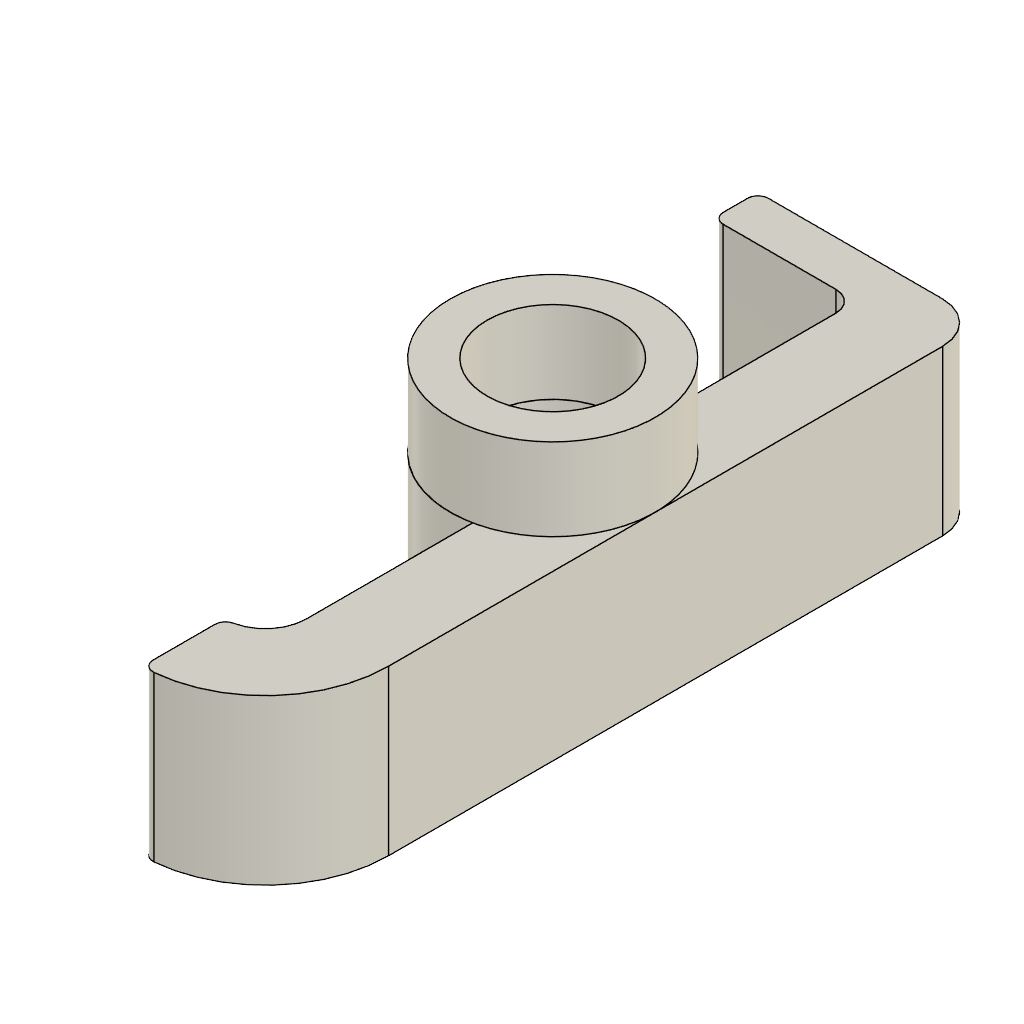
Top_Assembly_110626 (Autodesk Fusion 360 archive; units mm, degrees)
design "Bumper Flag"
part number: 2026-11-05-18-53-03-409
Autodesk Fusion 360 part; units mm, degrees
note: some values were not read from the file. Set by a fixed rule: which sketch regions a step uses.
sketch "Sketch1" plane through (0, 0, 0) normal (0, 0, 1) x (1, 0, 0)
  circle A0 centre (0, 0) radius 3.2
  line L0 (0, 0) -> (3.2, 0) construction
  circle A1 centre (0, 0) radius 5
  line L1 (3.2, 0) -> (5, 0) construction
  line L2 (5, 0) -> (5, -13)
  line L3 (5, -13) -> (-1, -13) construction
  arc A2 (-1, -19) -> (5, -13) centre (-1, -13) ccw
  line L4 (-1, -13) -> (-1, -19) construction
  line L5 (1, 4.899) -> (1, -13)
  arc A3 (-1, -15) -> (1, -13) centre (-1, -13) ccw
  line L6 (5, 0) -> (5, 16)
  line L7 (1, 4.899) -> (1, 13.8)
  line L8 (5, 16) -> (-6, 16)
  line L9 (1, 13.8) -> (-6, 13.8)
  line L10 (-6, 13.8) -> (-6, 16)
  circle A4 centre (-136.9792, 82.2137) radius 166.5 construction
  line L11 (-136.9792, 82.2137) -> (29.5208, 82.2137) construction
  line L12 (-136.9792, 82.2137) -> (0, 0) construction
  line L13 (0, 0) -> (5.7813, -3.4699) construction
  line L14 (0.2, 82.2137) -> (0.2, 15.461) construction
  line L15 (29.5208, 82.2137) -> (35.0208, 82.2137) construction
  line L16 (0.2, 15.461) -> (0.2, 12.961) construction
  line L17 (0.2, 12.961) -> (-5.8, 12.961) construction
  line L18 (-5.8, 12.961) -> (-5.8, 17.961) construction
  line L19 (0.2, 15.461) -> (-5.8, 15.461) construction
  line L20 (0.2, 17.961) -> (-5.8, 17.961) construction
  line L21 (-54.9792, 82.2137) -> (-54.9792, -11.7863) construction
  line L22 (-54.9792, -11.7863) -> (0.448, -11.7863) construction
  line L23 (-136.9792, 82.2137) -> (-136.9792, -89.7863) construction
  arc A5 (-136.9792, -89.7863) -> (-136.9792, 254.2137) centre (-136.9792, 82.2137) ccw
  line L24 (-136.9792, 82.2137) -> (-136.9792, 254.2137) construction
  line L25 (-136.9792, 82.2137) -> (-1, -13) construction
  line L26 (-1, -13) -> (3.9149, -16.4415) construction
  line L27 (4.5077, -2.1636) -> (-1.1176, -13.8835) construction
  line L28 (0, 0) -> (4.5077, -2.1636) construction
  line L29 (-1.1176, -13.8835) -> (-6.5268, -11.2872) construction
  arc A6 (-9.1231, -16.6964) -> (-1.1176, -13.8835) centre (-6.5268, -11.2872) ccw construction
  line L30 (-6.5268, -11.2872) -> (-9.1231, -16.6964) construction
  line L31 (-5.8, 12.961) -> (-5.8, 8.461) construction
  line L32 (0.2, 12.961) -> (0.2, 8.461) construction
  line L33 (0.2, 8.461) -> (-5.8, 8.461) construction
  line L34 (0.2, 22.461) -> (-5.8, 22.461) construction
  line L35 (-5.8, 17.961) -> (-5.8, 22.461) construction
  line L36 (0.2, 17.961) -> (0.2, 22.461) construction
  line L37 (4.5077, -2.1636) -> (11.4311, 12.2609) construction
  line L38 (11.4311, 12.2609) -> (1.5142, 17.0208) construction
  line L39 (1, 13.8) -> (1, 16) construction
  line L40 (1.5142, 17.0208) -> (0.5623, 15.0374) construction
  line L41 (0.5623, 15.0374) -> (6.873, 12.0084) construction
  line L42 (6.873, 12.0084) -> (3.0214, 3.9839) construction
  arc A7 (1.5142, 17.0208) -> (-6, 16) centre (0, 0) ccw construction
  arc A8 (0.5623, 15.0374) -> (-6, 13.8) centre (0, 0) ccw construction
  line L43 (0.2, 17.0868) -> (-5.8, 17.1571) construction
  line L44 (-2.8, 17.122) -> (-2.8, 17.961) construction
  line L45 (-2.5, 13.8) -> (-2.5, 12.961) construction
  line L46 (-1, -15) -> (-1, -19)
  point P0 (1, 14.9)
  point P1 (1, 14.9)
  point P2 (0.2, 17.0868)
  point P3 (0.2, 15.461)
  dimension "d2" = 3.2
  dimension "d4" = 5
  dimension "d5" = 6
  dimension "d6" = 13
  dimension "d8" = 4
  dimension "d12" = 16
  dimension "d24" = 166.5
  dimension "d30" = 5
  dimension "d32" = 172
  dimension "d33" = 94
  dimension "d34" = 35
  dimension "d36" = 90
  dimension "d38" = 0.2
  dimension "d39" = 6
  dimension "d44" = 4
  dimension "d45" = 7
  dimension "d47" = 2.2
  dimension "d50" = 7
  dimension "d52" = 0.839
  dimension "d53" = 66.7527
  dimension "d60" = 29.3208
  dimension "d61" = 30.972
  dimension "d62" = 6.7427
  dimension "d69" = 25.64
  constraint coincident A0.centre L0.start
  constraint coincident A0 L0.end
  constraint concentric A0 A1
  constraint coincident A1 L1.end
  constraint perpendicular A1 L1
  constraint tangent A1 L2
  constraint perpendicular L2 L3
  constraint coincident L3.end A2.centre
  constraint perpendicular L3 L4
  constraint coincident A1 L5.start
  constraint perpendicular L9 L10
  constraint coincident A4 L11.end
  constraint horizontal L11
  constraint coincident A4 L13.end
  constraint perpendicular A4 L13
  constraint coincident L11 L14.start
  constraint perpendicular L11 L14
  constraint parallel L14 L16
  constraint perpendicular L16 L17
  constraint perpendicular L17 L18
  constraint midpoint L18 L19.end
  constraint perpendicular L18 L19
  constraint symmetric L16.end L19 L20.start
  constraint symmetric L17.end L19 L18.end
  constraint coincident L11 L21.start
  constraint perpendicular L11 L21
  constraint coincident A4 L22.end
  constraint perpendicular L21 L22
  constraint coincident A4.centre L11.start
  constraint perpendicular L11 L23
  constraint symmetric L11 A4.centre L12.start
  constraint symmetric L11 L23.end A5.end
  constraint coincident L15.end A5
  constraint tangent A2 A5
  constraint coincident A5 L26.end
  constraint coincident A2 L26.end
  constraint perpendicular A5 L26
  constraint coincident A5.end L24.end
  constraint parallel L11 L15
  constraint coincident A1 L27.start
  constraint tangent A1 L27
  constraint equal L2 L27
  constraint perpendicular L27 L29
  constraint equal L3 L29
  constraint coincident L29.end A6.centre
  constraint perpendicular L29 L30
  constraint coincident A6.start L30.end
  constraint horizontal L9
  constraint perpendicular L17 L31
  constraint perpendicular L17 L32
  constraint perpendicular L32 L33
  constraint symmetric L19 L31.end L34.end
  constraint symmetric L19 L32.end L34.start
  constraint parallel L6 L7
  constraint parallel L2 L6
  constraint coincident L1.end L2.start
  constraint tangent A4 A6
  constraint tangent A1 L37
  constraint vertical L7
  constraint coincident L7.end L9.start
  constraint equal L6 L37
  constraint perpendicular L37 L38
  constraint horizontal L8
  constraint coincident L6.end L8.start
  constraint coincident L8 L39.end
  constraint perpendicular L8 L39
  constraint midpoint L39 P1
  constraint coincident P1 P0
  constraint equal L8 L38
  constraint perpendicular L38 L40
  constraint equal L10 L40
  constraint perpendicular L40 L41
  constraint equal L9 L41
  constraint perpendicular L41 L42
  constraint coincident A1 L42.end
  constraint coincident L38.end L40.start
  constraint coincident L8.end L10.end
  constraint coincident L40.end L41.start
  constraint coincident L9.end L10.start
  constraint coincident L14 P2
  constraint coincident A7 P2
  constraint coincident P2 L43.start
  constraint coincident L18 L43.end
  constraint tangent A7 L43
  constraint midpoint L43 L44.start
  constraint midpoint L20 L44.end
  constraint midpoint L9 L45.start
  constraint coincident L17 L45.end
  constraint perpendicular L17 L45
  constraint equal L44 L45
  constraint parallel L4 L46
  constraint coincident P3 L14.end
  measures "d2" radius of A0
  measures "d4" radius of A1
  measures "d5" radius of A2
  measures "d6" distance of L1.end L2.end
  measures "d12" distance of L1.end L6.end
  measures "d24" radius of A4
  measures "d30" distance of L17.end L18.end
  measures "d32" radius of A5
  measures "d33" distance of L21.start L21.end
  measures "d34" angle of L11 L25
  measures "d36" distance of L15.end L21.start
  measures "d38" distance of L10 L18
  measures "d39" distance of L20.start L18.end
  measures "d44" distance of L6 L7
  measures "d45" distance of L7.end L9.end
  measures "d47" distance of L8 L9
  measures "d50" distance of L19 L33
  measures "d52" distance of L45.start L45.end
  measures "d53" distance of L11 P3
  measures "d60" distance of L11.end L14
  measures "d61" angle of L11 L12
  measures "d62" distance of A0.centre L13.end
  measures "d69" angle of L0 L28
extrude "Extrude1" add sketch "Sketch1" along normal blind 8 contours A0 A1 L5 | A0 A1 L5 | A1 L6 L7 L8 L9 L10 | A1 L2 A2 L5 A3 L46 makes body 1
extrude "Extrude2" add sketch "Sketch1" along normal blind 4 from surface at 8 separate body contours A0 A1 L5 | A0 A1 L5 makes body 2
fillet "Fillet1" radius 0.5 4 edges at (-6, 13.8, 4) (-6, 16, 4) (-1, -15, 4) (-1, -19, 4) on bodies 1
fillet "Fillet1" radius 1 1 edges at (1, 13.8, 4) on bodies 1
fillet "Fillet1" radius 2 1 edges at (5, 16, 4) on bodies 1
mirror "Mirror1" about plane through (0, 0, 0) normal (0, 1, 0) of bodies 1 2 makes body 3 at (5, -5, 5.3333) makes body 4 at (4.9938, 0.2492, 10.6667)
hidden bodies 3 4
named bodies: "Flag R", "Spacer R", "Flag L", "Spacer L"

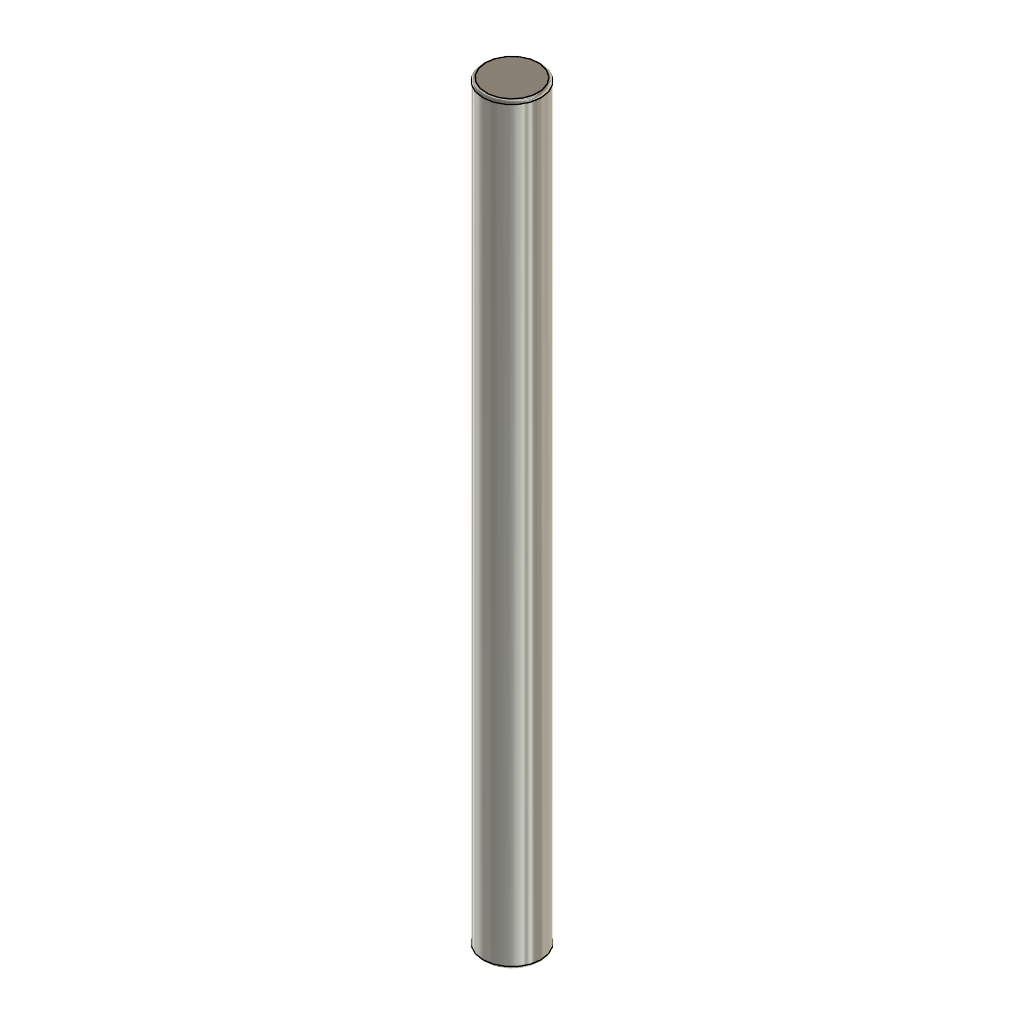
design "Pin 4mm Drive Wheel"
part number: 2026-10-28-22-08-27-820
Autodesk Fusion 360 part; units mm, degrees
sketch "Sketch1" plane through (0, 0, 0) normal (0, 0, 1) x (1, 0, 0)
  circle A0 centre (0, 0) radius 2
  dimension "d1" = 4
  constraint coincident A0.centre origin
  measures "d1" diameter of A0
extrude "Extrude1" add sketch "Sketch1" along normal blind 51.8
fillet "Fillet1" radius 0.2 2 edges at (-1.8647, -0.7232, 51.8) (-1.8647, -0.7232, 0)

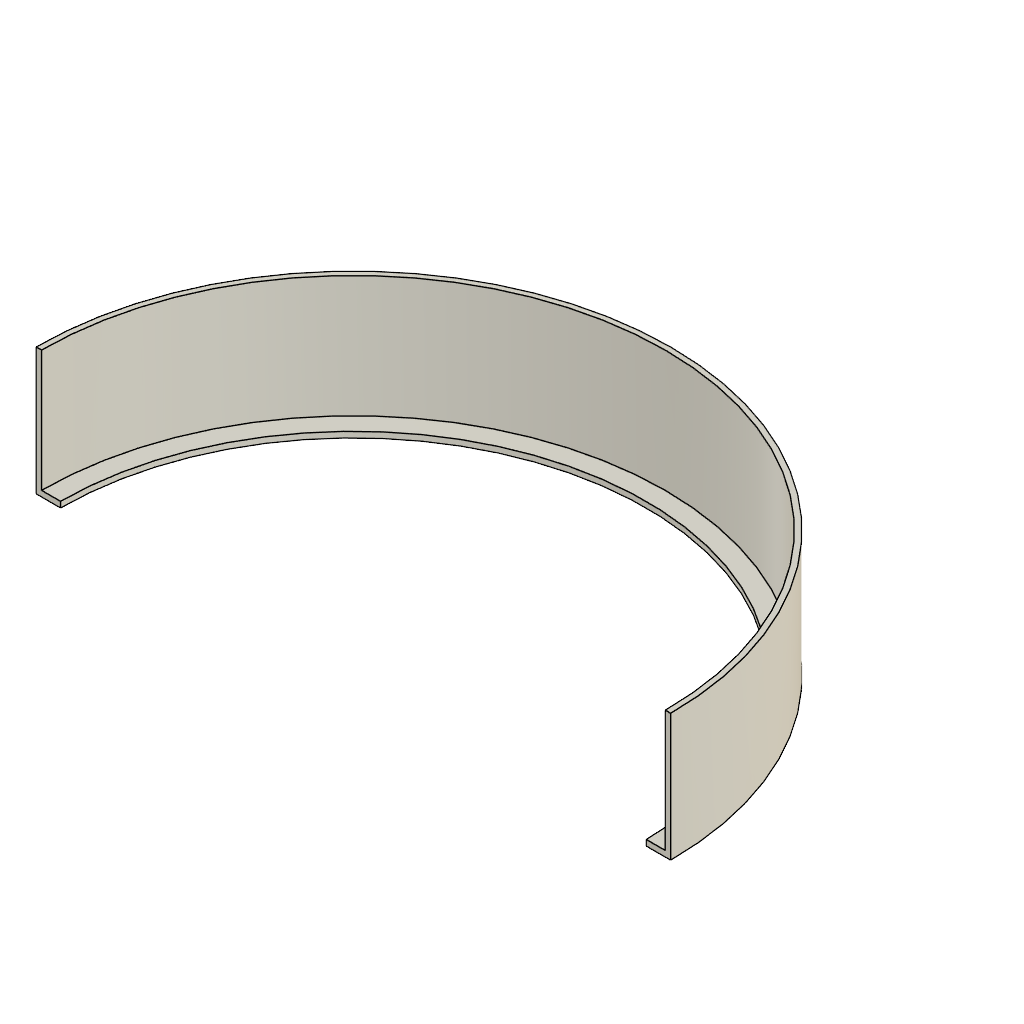
design "Bumper"
part number: 2026-11-05-22-16-40-985
Autodesk Fusion 360 part; units mm, degrees
sketch "Sketch1" plane through (0, 0, 0) normal (0, 0, 1) x (1, 0, 0)
  arc A0 (172, 0) -> (-172, 0) centre (0, 0) ccw
  line L0 (0, 0) -> (161.5, 0) construction
  line L1 (0, 0) -> (-161.5, 0) construction
  line L2 (172, 0) -> (175, 0)
  arc A1 (175, 0) -> (-175, 0) centre (0, 0) ccw
  line L3 (0, 0) -> (0, 172) construction
  line L4 (-172, 0) -> (-175, 0)
  arc A2 (161.5, 0) -> (-161.5, 0) centre (0, 0) ccw
  line L5 (161.5, 0) -> (172, 0)
  line L6 (-161.5, 0) -> (-172, 0)
  dimension "d1" = 172
  dimension "d2" = 3
  dimension "d5" = 13.5
  constraint coincident A0.centre L0.start
  constraint horizontal L0
  constraint parallel L0 L1
  constraint perpendicular A0 L2
  constraint midpoint A0 L3.end
  constraint symmetric A0.start L3 A0.end
  constraint symmetric L2.end L3 A1.end
  constraint coincident A1.end L4.end
  constraint coincident L1 L0.end
  constraint perpendicular A0 L5
  constraint perpendicular A0 L6
  measures "d1" radius of A0
  measures "d2" distance of A0.start L2.end
  measures "d5" distance of A1 A2
extrude "Extrude1" add sketch "Sketch1" along normal blind 67 contours A0 L2 A1 L4
extrude "Extrude2" add sketch "Sketch1" against normal blind 3.2
ref_plane "WorkPlane1" through (0, 87.5, 36.4) normal (0, 0, 1) x (1, 0, 0)
sketch "Joints" plane through (0, 0, 36.4) normal (0, 0, 1) x (1, 0, 0)
  line L0 (172, 0) -> (175, 0) construction
  arc A0 (175, 0) -> (-175, 0) centre (0, 0) ccw construction
  line L1 (-175, 0) -> (-172, 0) construction
  arc A1 (172, 0) -> (-172, 0) centre (0, 0) ccw construction

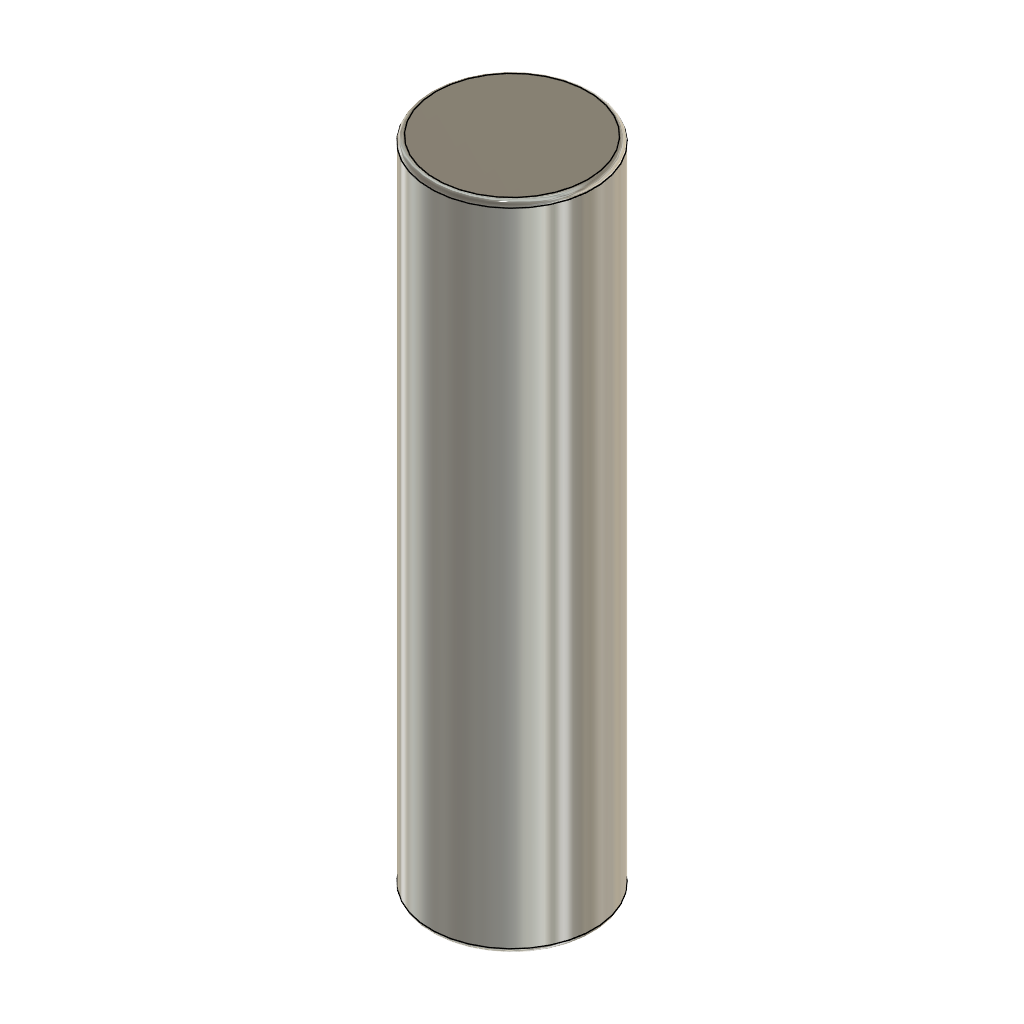
design "Dowel Pin D3 L12"
part number: 2026-10-20-12-42-43-443
Autodesk Fusion 360 part; units mm, degrees
sketch "Sketch1" plane through (0, 0, 0) normal (0, 0, 1) x (1, 0, 0)
  circle A0 centre (0, 0) radius 1.5
  dimension "d2" = 1.5
  constraint coincident A0.centre origin
  measures "d2" radius of A0
extrude "Extrude1" add sketch "Sketch1" along normal blind 12
fillet "Fillet1" radius 0.1 2 edges at (-1.3985, -0.5424, 12) (-1.3985, -0.5424, 0)
